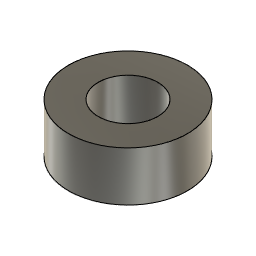
KOGUMA.MK3 (Autodesk Fusion 360 archive; units mm, degrees)
design "ベアリング（D６ｄ３）"
Autodesk Fusion 360 part; units mm, degrees
(part 1 of 8)
sketch "スケッチ1" plane through (0, 0, 0) normal (0, 0, 1) x (1, 0, 0)
  circle A0 centre (0, 0) radius 1.5
  circle A1 centre (0, 0) radius 3
  dimension "d1" = 3
  dimension "d2" = 6
  constraint coincident A0.centre A1.centre
  measures "d1" diameter of A0
  measures "d2" diameter of A1
extrude "押し出し1" add sketch "スケッチ1" along normal blind 2.5

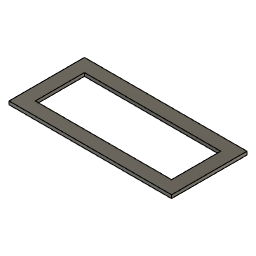
design "一次スカート"
Autodesk Fusion 360 part; units mm, degrees
sketch "スケッチ1" plane through (0, 0, 0) normal (0, 0, 1) x (1, 0, 0)
  line L0 (0, 0) -> (0, 15)
  line L1 (0, 15) -> (-41.568, 15)
  line L2 (-41.568, 15) -> (-41.568, 0)
  line L3 (-41.568, 0) -> (0, 0)
  line L4 (0, 0) -> (4, 0)
  line L5 (4, 0) -> (4, 1)
  line L6 (0, 15) -> (0, 19)
  line L7 (0, 19) -> (-64.5943, 19)
  line L8 (4, 0) -> (4, 52)
  line L9 (4, 19) -> (0, 19)
  line L10 (-41.568, 15) -> (-45.568, 15)
  line L11 (-45.568, 19) -> (-45.568, -8.7839)
  line L12 (-41.568, 0) -> (-41.568, -4)
  line L13 (-41.568, -4) -> (-45.568, -4)
  line L14 (-45.568, -4) -> (15, -4)
  line L15 (4, 0) -> (4, -9)
  dimension "d1" = 15
  dimension "d2" = 41.568
  dimension "d3" = 4
  dimension "d4" = 4
  dimension "d5" = 4
  dimension "d8" = 4
  dimension "d9" = 4
  constraint coincident L0.start L3.end
  constraint vertical L0
  constraint perpendicular L0 L1
  constraint perpendicular L1 L2
  constraint perpendicular L0 L3
  constraint perpendicular L0 L4
  constraint perpendicular L4 L5
  constraint perpendicular L1 L6
  constraint perpendicular L0 L7
  constraint perpendicular L4 L8
  constraint coincident L8 L9.start
  constraint perpendicular L6 L9
  constraint perpendicular L2 L10
  constraint coincident L7 L11.start
  constraint perpendicular L7 L11
  constraint perpendicular L3 L12
  constraint coincident L11 L13.end
  constraint perpendicular L11 L13
  constraint perpendicular L11 L14
  constraint perpendicular L14 L15
  measures "d1" distance of L0.start L0.end
  measures "d2" distance of L0.end L1.end
  measures "d3" distance of L0.start L4.end
  measures "d4" distance of L1.end L10.end
  measures "d5" distance of L2.end L12.end
  measures "d8" distance of L7 L10
  measures "d9" distance of L2 L11
extrude "押し出し1" add sketch "スケッチ1" along normal blind 1 contours L3 L4 L12 L14 L15 | L0 L4 L5 L6 L8 L9 | L1 L6 L7 L10 L11 | L2 L10 L11 L12 L13 L14
equation "d2 = ( 20.784 * 2 ) * 1 mm"

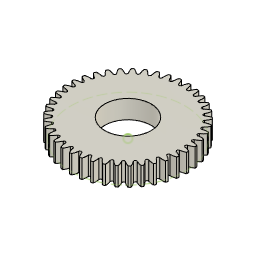
design "歯車M0.3T41"
description: Spur Gear; Module: 0.3; Num Teeth: 41; Pressure Angle: 20.0; Backlash: 0.00 mm
Autodesk Fusion 360 part; units mm, degrees
sketch "スケッチ1" plane through (0, 0, 0) normal (0, 0, 1) x (1, 0, 0) in component "Spur Gear (41 teeth)"
  circle A0 centre (0, 0) radius 5.7392
  circle A1 centre (0, 0) radius 0.5
extrude "押し出し1" add sketch "スケッチ1" along normal blind 2 contours A0 picked at (3.969571, -0.309968) in component "Spur Gear (41 teeth)"
sketch "スケッチ2" plane through (0, 0, 0) normal (0, 0, 1) x (1, 0, 0) in component "Spur Gear (41 teeth)"
  spline S0 degree 5 poles (5.770928, -0.307399) (5.77286, -0.307481) (5.776725, -0.30761) (5.782524, -0.307697) (5.79026, -0.307608) (5.799934, -0.307209) (5.809615, -0.30659) (5.819302, -0.30582) (5.828994, -0.304952) (5.838692, -0.304011) (5.848394, -0.303) (5.858099, -0.30191) (5.867807, -0.300726) (5.877517, -0.299436) (5.887228, -0.298039) (5.89694, -0.296542) (5.906654, -0.294955) (5.916369, -0.293289) (5.926086, -0.291553) (5.935804, -0.289752) (5.945522, -0.287885) (5.955241, -0.285952) (5.964961, -0.283951) (5.974681, -0.28188) (5.984401, -0.27974) (5.99412, -0.277533) (6.00384, -0.27526) (6.013559, -0.272926) (6.023279, -0.270532) (6.032997, -0.268079) (6.042715, -0.265569) (6.052432, -0.263001) (6.062149, -0.260375) (6.071864, -0.257693) (6.081578, -0.254954) (6.091292, -0.252159) (6.101003, -0.24931) (6.110714, -0.246406) (6.120423, -0.24345) (6.13013, -0.240441) (6.139836, -0.23738) (6.14954, -0.234268) (6.159242, -0.231105) (6.168942, -0.227891) (6.17864, -0.224627) (6.188336, -0.221314) (6.198029, -0.217951) (6.207721, -0.214539) (6.217409, -0.211079) (6.227096, -0.20757) (6.236779, -0.204015) (6.24646, -0.200412) (6.256138, -0.196762) (6.265814, -0.193065) (6.275486, -0.189323) (6.285155, -0.185534) (6.294822, -0.1817) (6.304485, -0.17782) (6.314144, -0.173896) (6.3238, -0.169926) (6.333453, -0.165912) (6.343102, -0.161854) (6.352748, -0.157752) (6.36239, -0.153607) (6.372028, -0.149418) (6.381663, -0.145185) (6.391293, -0.14091) (6.400919, -0.136592) (6.410541, -0.132232) (6.420159, -0.127829) (6.429773, -0.123385) (6.43746, -0.119795) (6.443224, -0.117084) (6.447066, -0.115268) (6.448986, -0.114359) knots 0 0 0 0 0 0 0.01428571 0.02857143 0.04285714 0.05714286 0.07142857 0.08571429 0.1 0.11428571 0.12857143 0.14285714 0.15714286 0.17142857 0.18571429 0.2 0.21428571 0.22857143 0.24285714 0.25714286 0.27142857 0.28571429 0.3 0.31428571 0.32857143 0.34285714 0.35714286 0.37142857 0.38571429 0.4 0.41428571 0.42857143 0.44285714 0.45714286 0.47142857 0.48571429 0.5 0.51428571 0.52857143 0.54285714 0.55714286 0.57142857 0.58571429 0.6 0.61428571 0.62857143 0.64285714 0.65714286 0.67142857 0.68571429 0.7 0.71428571 0.72857143 0.74285714 0.75714286 0.77142857 0.78571429 0.8 0.81428571 0.82857143 0.84285714 0.85714286 0.87142857 0.88571429 0.9 0.91428571 0.92857143 0.94285714 0.95714286 0.97142857 0.98571429 1 1 1 1 1 1
  spline S1 degree 5 poles (5.770928, 0.307399) (5.77286, 0.307481) (5.776725, 0.30761) (5.782524, 0.307697) (5.79026, 0.307608) (5.799934, 0.307209) (5.809615, 0.30659) (5.819302, 0.30582) (5.828994, 0.304952) (5.838692, 0.304011) (5.848394, 0.303) (5.858099, 0.30191) (5.867807, 0.300726) (5.877517, 0.299436) (5.887228, 0.298039) (5.89694, 0.296542) (5.906654, 0.294955) (5.916369, 0.293289) (5.926086, 0.291553) (5.935804, 0.289752) (5.945522, 0.287885) (5.955241, 0.285952) (5.964961, 0.283951) (5.974681, 0.28188) (5.984401, 0.27974) (5.99412, 0.277533) (6.00384, 0.27526) (6.013559, 0.272926) (6.023279, 0.270532) (6.032997, 0.268079) (6.042715, 0.265569) (6.052432, 0.263001) (6.062149, 0.260375) (6.071864, 0.257693) (6.081578, 0.254954) (6.091292, 0.252159) (6.101003, 0.24931) (6.110714, 0.246406) (6.120423, 0.24345) (6.13013, 0.240441) (6.139836, 0.23738) (6.14954, 0.234268) (6.159242, 0.231105) (6.168942, 0.227891) (6.17864, 0.224627) (6.188336, 0.221314) (6.198029, 0.217951) (6.207721, 0.214539) (6.217409, 0.211079) (6.227096, 0.20757) (6.236779, 0.204015) (6.24646, 0.200412) (6.256138, 0.196762) (6.265814, 0.193065) (6.275486, 0.189323) (6.285155, 0.185534) (6.294822, 0.1817) (6.304485, 0.17782) (6.314144, 0.173896) (6.3238, 0.169926) (6.333453, 0.165912) (6.343102, 0.161854) (6.352748, 0.157752) (6.36239, 0.153607) (6.372028, 0.149418) (6.381663, 0.145185) (6.391293, 0.14091) (6.400919, 0.136592) (6.410541, 0.132232) (6.420159, 0.127829) (6.429773, 0.123385) (6.43746, 0.119795) (6.443224, 0.117084) (6.447066, 0.115268) (6.448986, 0.114359) knots 0 0 0 0 0 0 0.01428571 0.02857143 0.04285714 0.05714286 0.07142857 0.08571429 0.1 0.11428571 0.12857143 0.14285714 0.15714286 0.17142857 0.18571429 0.2 0.21428571 0.22857143 0.24285714 0.25714286 0.27142857 0.28571429 0.3 0.31428571 0.32857143 0.34285714 0.35714286 0.37142857 0.38571429 0.4 0.41428571 0.42857143 0.44285714 0.45714286 0.47142857 0.48571429 0.5 0.51428571 0.52857143 0.54285714 0.55714286 0.57142857 0.58571429 0.6 0.61428571 0.62857143 0.64285714 0.65714286 0.67142857 0.68571429 0.7 0.71428571 0.72857143 0.74285714 0.75714286 0.77142857 0.78571429 0.8 0.81428571 0.82857143 0.84285714 0.85714286 0.87142857 0.88571429 0.9 0.91428571 0.92857143 0.94285714 0.95714286 0.97142857 0.98571429 1 1 1 1 1 1
  arc A0 (6.448986, -0.114359) -> (6.448986, 0.114359) centre (0, 0) ccw
  line L0 (5.721089, -0.305276) -> (5.770928, -0.307399)
  line L1 (5.721089, 0.305276) -> (5.770928, 0.307399)
  line L2 (5.721089, -0.305276) -> (5.721089, 0.305276)
  point P0 (5.819, -0.305821)
  point P1 (5.867247, -0.300771)
  point P2 (5.9156, -0.293406)
  point P3 (5.964028, -0.284129)
  point P4 (6.012511, -0.273166)
  point P5 (6.061031, -0.260666)
  point P6 (6.109575, -0.246736)
  point P7 (6.158127, -0.231458)
  point P8 (6.206677, -0.214896)
  point P9 (6.255212, -0.197101)
  point P10 (6.303722, -0.178116)
  point P11 (6.352194, -0.157978)
  point P12 (6.400619, -0.136716)
  point P13 (5.819, 0.305821)
  point P14 (5.867247, 0.300771)
  point P15 (5.9156, 0.293406)
  point P16 (5.964028, 0.284129)
  point P17 (6.012511, 0.273166)
  point P18 (6.061031, 0.260666)
  point P19 (6.109575, 0.246736)
  point P20 (6.158127, 0.231458)
  point P21 (6.206677, 0.214896)
  point P22 (6.255212, 0.197101)
  point P23 (6.303722, 0.178116)
  point P24 (6.352194, 0.157978)
  point P25 (6.400619, 0.136716)
extrude "押し出し2" add sketch "スケッチ2" along normal blind 2 contours S0 S1 A0 L0 L1 L2 picked at (6.064498, 0.076046) in component "Spur Gear (41 teeth)"
fillet "フィレット1" radius 0.15 2 edges at (5.731053, -0.3057, 1) (5.731053, 0.3057, 1) in component "Spur Gear (41 teeth)"
pattern_circular "C パターン1" count 41 over 360 about axis through (0, 0, 0) along (0, 0, 1) of "押し出し2", "フィレット1" in component "Spur Gear (41 teeth)"
sketch "スケッチ3" plane through (0, 0, 0) normal (0, 0, 1) x (1, 0, 0) in component "Spur Gear (41 teeth)"
  circle A0 centre (0, 0) radius 6.15 construction
sketch "スケッチ1 (2)" plane through (0, 0, 2) normal (0, 0, 1) x (-1, 0, 0)
  spline S0 degree 5 poles (-5.857066, 0.302007) (-5.857273, 0.301983) (-5.859421, 0.301733) (-5.86351, 0.301246) (-5.869542, 0.300495) (-5.877517, 0.299436) (-5.887228, 0.298039) (-5.89694, 0.296542) (-5.906654, 0.294955) (-5.916369, 0.293289) (-5.926086, 0.291553) (-5.935804, 0.289752) (-5.945522, 0.287885) (-5.955241, 0.285952) (-5.964961, 0.283951) (-5.974681, 0.28188) (-5.984401, 0.27974) (-5.99412, 0.277533) (-6.00384, 0.27526) (-6.013559, 0.272926) (-6.023279, 0.270532) (-6.032997, 0.268079) (-6.042715, 0.265569) (-6.052432, 0.263001) (-6.062149, 0.260375) (-6.071864, 0.257693) (-6.081578, 0.254954) (-6.091292, 0.252159) (-6.101003, 0.24931) (-6.110714, 0.246406) (-6.120423, 0.24345) (-6.13013, 0.240441) (-6.139836, 0.23738) (-6.14954, 0.234268) (-6.159242, 0.231105) (-6.168942, 0.227891) (-6.17864, 0.224627) (-6.188336, 0.221314) (-6.198029, 0.217951) (-6.207721, 0.214539) (-6.217409, 0.211079) (-6.227096, 0.20757) (-6.236779, 0.204015) (-6.24646, 0.200412) (-6.256138, 0.196762) (-6.265814, 0.193065) (-6.275486, 0.189323) (-6.285155, 0.185534) (-6.294822, 0.1817) (-6.304485, 0.17782) (-6.314144, 0.173896) (-6.3238, 0.169926) (-6.333453, 0.165912) (-6.343102, 0.161854) (-6.352748, 0.157752) (-6.36239, 0.153607) (-6.372028, 0.149418) (-6.381663, 0.145185) (-6.391293, 0.14091) (-6.400919, 0.136592) (-6.410541, 0.132232) (-6.420159, 0.127829) (-6.429773, 0.123385) (-6.43746, 0.119795) (-6.443224, 0.117084) (-6.447066, 0.115268) (-6.448986, 0.114359) knots 0.1270499 0.1270499 0.1270499 0.1270499 0.1270499 0.1270499 0.12857143 0.14285714 0.15714286 0.17142857 0.18571429 0.2 0.21428571 0.22857143 0.24285714 0.25714286 0.27142857 0.28571429 0.3 0.31428571 0.32857143 0.34285714 0.35714286 0.37142857 0.38571429 0.4 0.41428571 0.42857143 0.44285714 0.45714286 0.47142857 0.48571429 0.5 0.51428571 0.52857143 0.54285714 0.55714286 0.57142857 0.58571429 0.6 0.61428571 0.62857143 0.64285714 0.65714286 0.67142857 0.68571429 0.7 0.71428571 0.72857143 0.74285714 0.75714286 0.77142857 0.78571429 0.8 0.81428571 0.82857143 0.84285714 0.85714286 0.87142857 0.88571429 0.9 0.91428571 0.92857143 0.94285714 0.95714286 0.97142857 0.98571429 1 1 1 1 1 1
  arc A0 (-6.448986, 0.114359) -> (-6.448986, -0.114359) centre (0, 0) ccw
  spline S1 degree 5 poles (-6.448986, -0.114359) (-6.447066, -0.115268) (-6.443224, -0.117084) (-6.43746, -0.119795) (-6.429773, -0.123385) (-6.420159, -0.127829) (-6.410541, -0.132232) (-6.400919, -0.136592) (-6.391293, -0.14091) (-6.381663, -0.145185) (-6.372028, -0.149418) (-6.36239, -0.153607) (-6.352748, -0.157752) (-6.343102, -0.161854) (-6.333453, -0.165912) (-6.3238, -0.169926) (-6.314144, -0.173896) (-6.304485, -0.17782) (-6.294822, -0.1817) (-6.285155, -0.185534) (-6.275486, -0.189323) (-6.265814, -0.193065) (-6.256138, -0.196762) (-6.24646, -0.200412) (-6.236779, -0.204015) (-6.227096, -0.20757) (-6.217409, -0.211079) (-6.207721, -0.214539) (-6.198029, -0.217951) (-6.188336, -0.221314) (-6.17864, -0.224627) (-6.168942, -0.227891) (-6.159242, -0.231105) (-6.14954, -0.234268) (-6.139836, -0.23738) (-6.13013, -0.240441) (-6.120423, -0.24345) (-6.110714, -0.246406) (-6.101003, -0.24931) (-6.091292, -0.252159) (-6.081578, -0.254954) (-6.071864, -0.257693) (-6.062149, -0.260375) (-6.052432, -0.263001) (-6.042715, -0.265569) (-6.032997, -0.268079) (-6.023279, -0.270532) (-6.013559, -0.272926) (-6.00384, -0.27526) (-5.99412, -0.277533) (-5.984401, -0.27974) (-5.974681, -0.28188) (-5.964961, -0.283951) (-5.955241, -0.285952) (-5.945522, -0.287885) (-5.935804, -0.289752) (-5.926086, -0.291553) (-5.916369, -0.293289) (-5.906654, -0.294955) (-5.89694, -0.296542) (-5.887228, -0.298039) (-5.877517, -0.299436) (-5.869542, -0.300495) (-5.86351, -0.301246) (-5.859421, -0.301733) (-5.857273, -0.301983) (-5.857066, -0.302007) knots -1 -1 -1 -1 -1 -1 -0.98571429 -0.97142857 -0.95714286 -0.94285714 -0.92857143 -0.91428571 -0.9 -0.88571429 -0.87142857 -0.85714286 -0.84285714 -0.82857143 -0.81428571 -0.8 -0.78571429 -0.77142857 -0.75714286 -0.74285714 -0.72857143 -0.71428571 -0.7 -0.68571429 -0.67142857 -0.65714286 -0.64285714 -0.62857143 -0.61428571 -0.6 -0.58571429 -0.57142857 -0.55714286 -0.54285714 -0.52857143 -0.51428571 -0.5 -0.48571429 -0.47142857 -0.45714286 -0.44285714 -0.42857143 -0.41428571 -0.4 -0.38571429 -0.37142857 -0.35714286 -0.34285714 -0.32857143 -0.31428571 -0.3 -0.28571429 -0.27142857 -0.25714286 -0.24285714 -0.22857143 -0.21428571 -0.2 -0.18571429 -0.17142857 -0.15714286 -0.14285714 -0.12857143 -0.1270499 -0.1270499 -0.1270499 -0.1270499 -0.1270499 -0.1270499
  spline S2 degree 3 poles (-5.834525, -0.595609) (-5.815695, -0.590418) (-5.798059, -0.581599) (-5.76716, -0.557697) (-5.754193, -0.542842) (-5.734682, -0.508999) (-5.728326, -0.490334) (-5.723124, -0.451617) (-5.724329, -0.431936) (-5.734216, -0.394144) (-5.742803, -0.376393) (-5.766298, -0.345184) (-5.780981, -0.332023) (-5.806816, -0.316674) (-5.816398, -0.312267) (-5.836327, -0.305532) (-5.846618, -0.303222) (-5.857066, -0.302007) knots 0 0 0 0 0.00585967 0.00585967 0.01171933 0.01171933 0.017579 0.017579 0.02343867 0.02343867 0.02929834 0.02929834 0.035158 0.035158 0.03831344 0.03831344 0.04146887 0.04146887 0.04146887 0.04146887
  spline S3 degree 5 poles (-5.834525, -0.595609) (-5.834725, -0.595664) (-5.83681, -0.59624) (-5.840777, -0.597346) (-5.846624, -0.599008) (-5.854343, -0.601272) (-5.863727, -0.604135) (-5.873098, -0.607097) (-5.882455, -0.610148) (-5.891802, -0.613278) (-5.90114, -0.616476) (-5.910469, -0.61974) (-5.919789, -0.623068) (-5.929099, -0.626462) (-5.938399, -0.629924) (-5.947689, -0.633454) (-5.956968, -0.637053) (-5.966237, -0.640718) (-5.975496, -0.644447) (-5.984745, -0.648238) (-5.993985, -0.652088) (-6.003215, -0.655995) (-6.012436, -0.65996) (-6.021647, -0.663981) (-6.030849, -0.668059) (-6.040041, -0.672193) (-6.049223, -0.676383) (-6.058396, -0.680627) (-6.067559, -0.684926) (-6.076713, -0.689278) (-6.085857, -0.693681) (-6.094991, -0.698137) (-6.104116, -0.702643) (-6.113231, -0.7072) (-6.122336, -0.711807) (-6.131432, -0.716464) (-6.140518, -0.72117) (-6.149595, -0.725925) (-6.158661, -0.730728) (-6.167718, -0.73558) (-6.176765, -0.740478) (-6.185802, -0.745424) (-6.19483, -0.750416) (-6.203847, -0.755455) (-6.212855, -0.760539) (-6.221852, -0.765669) (-6.23084, -0.770845) (-6.239818, -0.776065) (-6.248785, -0.78133) (-6.257743, -0.786639) (-6.26669, -0.791992) (-6.275627, -0.797389) (-6.284554, -0.802829) (-6.293471, -0.808312) (-6.302377, -0.813839) (-6.311274, -0.819408) (-6.320159, -0.825019) (-6.329035, -0.830672) (-6.337899, -0.836368) (-6.346754, -0.842104) (-6.355597, -0.847882) (-6.36443, -0.853701) (-6.373253, -0.859562) (-6.380302, -0.864282) (-6.385585, -0.867841) (-6.389104, -0.870222) (-6.390863, -0.871415) knots 0.1270499 0.1270499 0.1270499 0.1270499 0.1270499 0.1270499 0.12857143 0.14285714 0.15714286 0.17142857 0.18571429 0.2 0.21428571 0.22857143 0.24285714 0.25714286 0.27142857 0.28571429 0.3 0.31428571 0.32857143 0.34285714 0.35714286 0.37142857 0.38571429 0.4 0.41428571 0.42857143 0.44285714 0.45714286 0.47142857 0.48571429 0.5 0.51428571 0.52857143 0.54285714 0.55714286 0.57142857 0.58571429 0.6 0.61428571 0.62857143 0.64285714 0.65714286 0.67142857 0.68571429 0.7 0.71428571 0.72857143 0.74285714 0.75714286 0.77142857 0.78571429 0.8 0.81428571 0.82857143 0.84285714 0.85714286 0.87142857 0.88571429 0.9 0.91428571 0.92857143 0.94285714 0.95714286 0.97142857 0.98571429 1 1 1 1 1 1
  arc A1 (-6.390863, -0.871415) -> (-6.35595, -1.097451) centre (0, 0) ccw
  spline S4 degree 5 poles (-6.35595, -1.097451) (-6.353913, -1.098058) (-6.349839, -1.099266) (-6.343729, -1.101065) (-6.335584, -1.103439) (-6.325404, -1.106364) (-6.315227, -1.109247) (-6.305052, -1.112087) (-6.29488, -1.114885) (-6.28471, -1.11764) (-6.274542, -1.120352) (-6.264378, -1.123021) (-6.254216, -1.125646) (-6.244057, -1.128228) (-6.233901, -1.130765) (-6.223749, -1.133258) (-6.2136, -1.135707) (-6.203455, -1.138111) (-6.193313, -1.14047) (-6.183174, -1.142784) (-6.17304, -1.145052) (-6.16291, -1.147275) (-6.152784, -1.149451) (-6.142662, -1.151581) (-6.132544, -1.153664) (-6.122431, -1.1557) (-6.112323, -1.157688) (-6.10222, -1.159629) (-6.092121, -1.161521) (-6.082028, -1.163365) (-6.07194, -1.16516) (-6.061857, -1.166905) (-6.05178, -1.168601) (-6.041709, -1.170246) (-6.031644, -1.17184) (-6.021585, -1.173383) (-6.011532, -1.174875) (-6.001485, -1.176315) (-5.991445, -1.177702) (-5.981412, -1.179035) (-5.971386, -1.180314) (-5.961368, -1.181538) (-5.951357, -1.182706) (-5.941354, -1.183818) (-5.931358, -1.184872) (-5.921371, -1.18587) (-5.911392, -1.18681) (-5.901421, -1.187693) (-5.891459, -1.188516) (-5.881507, -1.189278) (-5.871564, -1.189976) (-5.861631, -1.190608) (-5.851709, -1.19117) (-5.841798, -1.191664) (-5.831898, -1.192091) (-5.822008, -1.192452) (-5.812129, -1.192749) (-5.802262, -1.192981) (-5.792406, -1.193145) (-5.782564, -1.193231) (-5.772736, -1.193227) (-5.762926, -1.193125) (-5.754883, -1.192955) (-5.748807, -1.192776) (-5.744691, -1.192633) (-5.74253, -1.192552) (-5.742322, -1.192545) knots -1 -1 -1 -1 -1 -1 -0.98571429 -0.97142857 -0.95714286 -0.94285714 -0.92857143 -0.91428571 -0.9 -0.88571429 -0.87142857 -0.85714286 -0.84285714 -0.82857143 -0.81428571 -0.8 -0.78571429 -0.77142857 -0.75714286 -0.74285714 -0.72857143 -0.71428571 -0.7 -0.68571429 -0.67142857 -0.65714286 -0.64285714 -0.62857143 -0.61428571 -0.6 -0.58571429 -0.57142857 -0.55714286 -0.54285714 -0.52857143 -0.51428571 -0.5 -0.48571429 -0.47142857 -0.45714286 -0.44285714 -0.42857143 -0.41428571 -0.4 -0.38571429 -0.37142857 -0.35714286 -0.34285714 -0.32857143 -0.31428571 -0.3 -0.28571429 -0.27142857 -0.25714286 -0.24285714 -0.22857143 -0.21428571 -0.2 -0.18571429 -0.17142857 -0.15714286 -0.14285714 -0.12857143 -0.1270499 -0.1270499 -0.1270499 -0.1270499 -0.1270499 -0.1270499
  spline S5 degree 3 poles (-5.675227, -1.479265) (-5.65741, -1.47126) (-5.641328, -1.459852) (-5.61444, -1.431514) (-5.603892, -1.414854) (-5.589776, -1.378429) (-5.586343, -1.359012) (-5.587113, -1.319955) (-5.591308, -1.300689) (-5.606848, -1.264848) (-5.618044, -1.248617) (-5.646027, -1.22136) (-5.662547, -1.210594) (-5.690422, -1.199369) (-5.700565, -1.196477) (-5.721289, -1.192863) (-5.731812, -1.19215) (-5.742322, -1.192545) knots 0 0 0 0 0.00585967 0.00585967 0.01171933 0.01171933 0.017579 0.017579 0.02343867 0.02343867 0.02929834 0.02929834 0.035158 0.035158 0.03831344 0.03831344 0.04146887 0.04146887 0.04146887 0.04146887
  spline S6 degree 5 poles (-5.675227, -1.479265) (-5.675417, -1.47935) (-5.677389, -1.480237) (-5.681141, -1.481935) (-5.686666, -1.484471) (-5.693949, -1.487887) (-5.702786, -1.492148) (-5.711595, -1.496506) (-5.720377, -1.50095) (-5.729137, -1.50547) (-5.737877, -1.510056) (-5.746598, -1.514706) (-5.7553, -1.519418) (-5.763983, -1.524193) (-5.772646, -1.529033) (-5.781288, -1.533941) (-5.789909, -1.538914) (-5.79851, -1.543951) (-5.807091, -1.54905) (-5.815653, -1.554208) (-5.824197, -1.559423) (-5.832723, -1.564694) (-5.84123, -1.570019) (-5.84972, -1.5754) (-5.858191, -1.580834) (-5.866645, -1.586323) (-5.87508, -1.591866) (-5.883497, -1.597461) (-5.891896, -1.603108) (-5.900278, -1.608805) (-5.908643, -1.614553) (-5.91699, -1.620351) (-5.92532, -1.626197) (-5.933633, -1.632092) (-5.941928, -1.638035) (-5.950207, -1.644026) (-5.958468, -1.650064) (-5.966712, -1.656149) (-5.974939, -1.66228) (-5.983149, -1.668457) (-5.991342, -1.674679) (-5.999519, -1.680946) (-6.007678, -1.687258) (-6.015821, -1.693614) (-6.023947, -1.700014) (-6.032056, -1.706457) (-6.040148, -1.712944) (-6.048224, -1.719473) (-6.056283, -1.726045) (-6.064325, -1.73266) (-6.07235, -1.739316) (-6.080359, -1.746014) (-6.088351, -1.752753) (-6.096326, -1.759533) (-6.104284, -1.766354) (-6.112226, -1.773216) (-6.120151, -1.780118) (-6.128059, -1.78706) (-6.135951, -1.794041) (-6.143826, -1.801063) (-6.151684, -1.808123) (-6.159525, -1.815222) (-6.16735, -1.82236) (-6.173596, -1.828102) (-6.178273, -1.832426) (-6.181388, -1.835316) (-6.182944, -1.836763) knots 0.1270499 0.1270499 0.1270499 0.1270499 0.1270499 0.1270499 0.12857143 0.14285714 0.15714286 0.17142857 0.18571429 0.2 0.21428571 0.22857143 0.24285714 0.25714286 0.27142857 0.28571429 0.3 0.31428571 0.32857143 0.34285714 0.35714286 0.37142857 0.38571429 0.4 0.41428571 0.42857143 0.44285714 0.45714286 0.47142857 0.48571429 0.5 0.51428571 0.52857143 0.54285714 0.55714286 0.57142857 0.58571429 0.6 0.61428571 0.62857143 0.64285714 0.65714286 0.67142857 0.68571429 0.7 0.71428571 0.72857143 0.74285714 0.75714286 0.77142857 0.78571429 0.8 0.81428571 0.82857143 0.84285714 0.85714286 0.87142857 0.88571429 0.9 0.91428571 0.92857143 0.94285714 0.95714286 0.97142857 0.98571429 1 1 1 1 1 1
  arc A2 (-6.182944, -1.836763) -> (-6.113936, -2.054821) centre (0, 0) ccw
  spline S7 degree 5 poles (-6.113936, -2.054821) (-6.11183, -2.055109) (-6.10762, -2.055681) (-6.101307, -2.056527) (-6.092894, -2.057629) (-6.082388, -2.058966) (-6.07189, -2.060262) (-6.0614, -2.061516) (-6.05092, -2.062728) (-6.040449, -2.063898) (-6.029986, -2.065026) (-6.019533, -2.066112) (-6.00909, -2.067156) (-5.998656, -2.068156) (-5.988232, -2.069114) (-5.977818, -2.070028) (-5.967414, -2.070899) (-5.957021, -2.071726) (-5.946638, -2.072509) (-5.936265, -2.073248) (-5.925903, -2.073943) (-5.915552, -2.074593) (-5.905213, -2.075198) (-5.894884, -2.075758) (-5.884567, -2.076272) (-5.874262, -2.07674) (-5.863969, -2.077162) (-5.853688, -2.077538) (-5.843419, -2.077866) (-5.833162, -2.078148) (-5.822918, -2.078382) (-5.812688, -2.078568) (-5.80247, -2.078705) (-5.792266, -2.078793) (-5.782075, -2.078833) (-5.771898, -2.078822) (-5.761735, -2.078762) (-5.751587, -2.078651) (-5.741453, -2.078489) (-5.731334, -2.078276) (-5.72123, -2.078009) (-5.711142, -2.07769) (-5.70107, -2.077316) (-5.691014, -2.076887) (-5.680975, -2.076404) (-5.670953, -2.075865) (-5.660947, -2.075271) (-5.650959, -2.074621) (-5.640988, -2.073914) (-5.631035, -2.073148) (-5.621103, -2.07232) (-5.61119, -2.071428) (-5.601298, -2.07047) (-5.591428, -2.069445) (-5.581578, -2.068355) (-5.57175, -2.067202) (-5.561941, -2.065988) (-5.552154, -2.064711) (-5.542389, -2.063368) (-5.532649, -2.061951) (-5.522937, -2.060447) (-5.513257, -2.058849) (-5.505335, -2.057453) (-5.499357, -2.056348) (-5.495311, -2.055579) (-5.493188, -2.055169) (-5.492984, -2.05513) knots -1 -1 -1 -1 -1 -1 -0.98571429 -0.97142857 -0.95714286 -0.94285714 -0.92857143 -0.91428571 -0.9 -0.88571429 -0.87142857 -0.85714286 -0.84285714 -0.82857143 -0.81428571 -0.8 -0.78571429 -0.77142857 -0.75714286 -0.74285714 -0.72857143 -0.71428571 -0.7 -0.68571429 -0.67142857 -0.65714286 -0.64285714 -0.62857143 -0.61428571 -0.6 -0.58571429 -0.57142857 -0.55714286 -0.54285714 -0.52857143 -0.51428571 -0.5 -0.48571429 -0.47142857 -0.45714286 -0.44285714 -0.42857143 -0.41428571 -0.4 -0.38571429 -0.37142857 -0.35714286 -0.34285714 -0.32857143 -0.31428571 -0.3 -0.28571429 -0.27142857 -0.25714286 -0.24285714 -0.22857143 -0.21428571 -0.2 -0.18571429 -0.17142857 -0.15714286 -0.14285714 -0.12857143 -0.1270499 -0.1270499 -0.1270499 -0.1270499 -0.1270499 -0.1270499
  spline S8 degree 3 poles (-5.382907, -2.328248) (-5.366521, -2.317618) (-5.352368, -2.303888) (-5.330121, -2.271777) (-5.32224, -2.253703) (-5.31385, -2.21555) (-5.313421, -2.195836) (-5.320144, -2.157355) (-5.327231, -2.138955) (-5.34806, -2.105906) (-5.361602, -2.091574) (-5.393419, -2.068908) (-5.411388, -2.06079) (-5.44065, -2.053952) (-5.451116, -2.052642) (-5.472148, -2.052233) (-5.482656, -2.053136) (-5.492984, -2.05513) knots 0 0 0 0 0.00585967 0.00585967 0.01171933 0.01171933 0.017579 0.017579 0.02343867 0.02343867 0.02929834 0.02929834 0.035158 0.035158 0.03831344 0.03831344 0.04146887 0.04146887 0.04146887 0.04146887
  spline S9 degree 5 poles (-5.382907, -2.328248) (-5.383082, -2.328361) (-5.384896, -2.329539) (-5.388344, -2.33179) (-5.393417, -2.335139) (-5.400093, -2.339627) (-5.408177, -2.345187) (-5.416216, -2.350839) (-5.424218, -2.356571) (-5.432185, -2.362375) (-5.440122, -2.368242) (-5.448031, -2.374168) (-5.455912, -2.380153) (-5.463765, -2.386198) (-5.471587, -2.392304) (-5.479379, -2.398473) (-5.48714, -2.404704) (-5.494871, -2.410995) (-5.502573, -2.417344) (-5.510248, -2.423749) (-5.517895, -2.430207) (-5.525516, -2.436717) (-5.533111, -2.443279) (-5.54068, -2.449892) (-5.548223, -2.456556) (-5.555739, -2.463271) (-5.563229, -2.470036) (-5.570694, -2.476851) (-5.578133, -2.483714) (-5.585547, -2.490624) (-5.592936, -2.497582) (-5.6003, -2.504585) (-5.60764, -2.511635) (-5.614955, -2.51873) (-5.622246, -2.525869) (-5.629513, -2.533053) (-5.636756, -2.540282) (-5.643975, -2.547554) (-5.651169, -2.554869) (-5.658341, -2.562227) (-5.665488, -2.569627) (-5.672612, -2.577068) (-5.679712, -2.584552) (-5.686789, -2.592076) (-5.693843, -2.599642) (-5.700873, -2.607247) (-5.707881, -2.614893) (-5.714865, -2.622579) (-5.721826, -2.630304) (-5.728764, -2.638069) (-5.735679, -2.645872) (-5.742572, -2.653714) (-5.749441, -2.661594) (-5.756288, -2.669512) (-5.763112, -2.677468) (-5.769913, -2.685462) (-5.776692, -2.693492) (-5.783448, -2.70156) (-5.790181, -2.709665) (-5.796892, -2.717805) (-5.80358, -2.725983) (-5.810246, -2.734196) (-5.816889, -2.742445) (-5.822186, -2.749072) (-5.826148, -2.754059) (-5.828785, -2.757391) (-5.830102, -2.759059) knots 0.1270499 0.1270499 0.1270499 0.1270499 0.1270499 0.1270499 0.12857143 0.14285714 0.15714286 0.17142857 0.18571429 0.2 0.21428571 0.22857143 0.24285714 0.25714286 0.27142857 0.28571429 0.3 0.31428571 0.32857143 0.34285714 0.35714286 0.37142857 0.38571429 0.4 0.41428571 0.42857143 0.44285714 0.45714286 0.47142857 0.48571429 0.5 0.51428571 0.52857143 0.54285714 0.55714286 0.57142857 0.58571429 0.6 0.61428571 0.62857143 0.64285714 0.65714286 0.67142857 0.68571429 0.7 0.71428571 0.72857143 0.74285714 0.75714286 0.77142857 0.78571429 0.8 0.81428571 0.82857143 0.84285714 0.85714286 0.87142857 0.88571429 0.9 0.91428571 0.92857143 0.94285714 0.95714286 0.97142857 0.98571429 1 1 1 1 1 1
  arc A3 (-5.830102, -2.759059) -> (-5.728616, -2.964027) centre (0, 0) ccw
  spline S10 degree 5 poles (-5.728616, -2.964027) (-5.726491, -2.963991) (-5.722243, -2.963913) (-5.715875, -2.963785) (-5.707393, -2.963591) (-5.696805, -2.963308) (-5.686232, -2.962986) (-5.675675, -2.962624) (-5.665132, -2.962222) (-5.654605, -2.96178) (-5.644093, -2.961298) (-5.633597, -2.960776) (-5.623116, -2.960213) (-5.612652, -2.959609) (-5.602204, -2.958964) (-5.591772, -2.958278) (-5.581358, -2.95755) (-5.57096, -2.956781) (-5.560579, -2.95597) (-5.550215, -2.955117) (-5.539868, -2.954222) (-5.52954, -2.953284) (-5.519229, -2.952304) (-5.508936, -2.95128) (-5.498661, -2.950214) (-5.488406, -2.949103) (-5.478168, -2.947949) (-5.46795, -2.946751) (-5.457751, -2.945508) (-5.447572, -2.944221) (-5.437413, -2.942889) (-5.427273, -2.94151) (-5.417155, -2.940086) (-5.407056, -2.938616) (-5.396979, -2.937099) (-5.386923, -2.935535) (-5.376889, -2.933924) (-5.366876, -2.932266) (-5.356886, -2.930559) (-5.346918, -2.928803) (-5.336973, -2.926998) (-5.327052, -2.925142) (-5.317155, -2.923235) (-5.307283, -2.921276) (-5.297435, -2.919266) (-5.287612, -2.917204) (-5.277814, -2.915089) (-5.268042, -2.912922) (-5.258296, -2.910702) (-5.248578, -2.908425) (-5.238887, -2.906091) (-5.229227, -2.903696) (-5.219598, -2.901239) (-5.209999, -2.898719) (-5.200432, -2.896139) (-5.190894, -2.893499) (-5.181386, -2.890802) (-5.171908, -2.888046) (-5.162463, -2.885228) (-5.153053, -2.88234) (-5.143685, -2.879372) (-5.134362, -2.876315) (-5.126746, -2.873726) (-5.121007, -2.871722) (-5.117126, -2.870344) (-5.11509, -2.869615) (-5.114894, -2.869545) knots -1 -1 -1 -1 -1 -1 -0.98571429 -0.97142857 -0.95714286 -0.94285714 -0.92857143 -0.91428571 -0.9 -0.88571429 -0.87142857 -0.85714286 -0.84285714 -0.82857143 -0.81428571 -0.8 -0.78571429 -0.77142857 -0.75714286 -0.74285714 -0.72857143 -0.71428571 -0.7 -0.68571429 -0.67142857 -0.65714286 -0.64285714 -0.62857143 -0.61428571 -0.6 -0.58571429 -0.57142857 -0.55714286 -0.54285714 -0.52857143 -0.51428571 -0.5 -0.48571429 -0.47142857 -0.45714286 -0.44285714 -0.42857143 -0.41428571 -0.4 -0.38571429 -0.37142857 -0.35714286 -0.34285714 -0.32857143 -0.31428571 -0.3 -0.28571429 -0.27142857 -0.25714286 -0.24285714 -0.22857143 -0.21428571 -0.2 -0.18571429 -0.17142857 -0.15714286 -0.14285714 -0.12857143 -0.1270499 -0.1270499 -0.1270499 -0.1270499 -0.1270499 -0.1270499
  spline S11 degree 3 poles (-4.964416, -3.122659) (-4.949845, -3.109652) (-4.937954, -3.093923) (-4.920869, -3.058792) (-4.91584, -3.039726) (-4.913372, -3.00074) (-4.915957, -2.981192) (-4.928475, -2.944188) (-4.938288, -2.927085) (-4.963918, -2.897603) (-4.979489, -2.885507) (-5.014393, -2.867963) (-5.033391, -2.862683) (-5.063354, -2.860392) (-5.073896, -2.860695) (-5.094745, -2.863501) (-5.104992, -2.865997) (-5.114894, -2.869545) knots 0 0 0 0 0.00585967 0.00585967 0.01171933 0.01171933 0.017579 0.017579 0.02343867 0.02343867 0.02929834 0.02929834 0.035158 0.035158 0.03831344 0.03831344 0.04146887 0.04146887 0.04146887 0.04146887
  spline S12 degree 5 poles (-4.964416, -3.122659) (-4.964572, -3.122797) (-4.966185, -3.124238) (-4.969249, -3.126989) (-4.973751, -3.131073) (-4.979664, -3.136528) (-4.986804, -3.143257) (-4.993887, -3.150069) (-5.000919, -3.156956) (-5.007907, -3.163908) (-5.014856, -3.170918) (-5.021768, -3.177982) (-5.028643, -3.1851) (-5.03548, -3.192273) (-5.042279, -3.199501) (-5.049038, -3.206787) (-5.055757, -3.21413) (-5.062437, -3.221527) (-5.069079, -3.228978) (-5.075686, -3.236479) (-5.082258, -3.244029) (-5.088796, -3.251626) (-5.095301, -3.25927) (-5.101771, -3.266961) (-5.108208, -3.274699) (-5.114611, -3.282482) (-5.120981, -3.290311) (-5.127318, -3.298185) (-5.133622, -3.306104) (-5.139894, -3.314065) (-5.146135, -3.322069) (-5.152344, -3.330115) (-5.158522, -3.338202) (-5.164668, -3.34633) (-5.170784, -3.354499) (-5.176869, -3.362708) (-5.182923, -3.370958) (-5.188947, -3.379246) (-5.194941, -3.387574) (-5.200905, -3.39594) (-5.206839, -3.404344) (-5.212744, -3.412786) (-5.218618, -3.421266) (-5.224464, -3.429783) (-5.23028, -3.438336) (-5.236067, -3.446926) (-5.241825, -3.455552) (-5.247554, -3.464213) (-5.253255, -3.472911) (-5.258926, -3.481643) (-5.264569, -3.490411) (-5.270184, -3.499213) (-5.27577, -3.508049) (-5.281328, -3.51692) (-5.286857, -3.525824) (-5.292359, -3.534762) (-5.297832, -3.543734) (-5.303277, -3.552738) (-5.308694, -3.561776) (-5.314084, -3.570845) (-5.319445, -3.579948) (-5.324779, -3.589082) (-5.330085, -3.598248) (-5.334308, -3.605607) (-5.337463, -3.61114) (-5.33956, -3.614836) (-5.340608, -3.616685) knots 0.1270499 0.1270499 0.1270499 0.1270499 0.1270499 0.1270499 0.12857143 0.14285714 0.15714286 0.17142857 0.18571429 0.2 0.21428571 0.22857143 0.24285714 0.25714286 0.27142857 0.28571429 0.3 0.31428571 0.32857143 0.34285714 0.35714286 0.37142857 0.38571429 0.4 0.41428571 0.42857143 0.44285714 0.45714286 0.47142857 0.48571429 0.5 0.51428571 0.52857143 0.54285714 0.55714286 0.57142857 0.58571429 0.6 0.61428571 0.62857143 0.64285714 0.65714286 0.67142857 0.68571429 0.7 0.71428571 0.72857143 0.74285714 0.75714286 0.77142857 0.78571429 0.8 0.81428571 0.82857143 0.84285714 0.85714286 0.87142857 0.88571429 0.9 0.91428571 0.92857143 0.94285714 0.95714286 0.97142857 0.98571429 1 1 1 1 1 1
  arc A4 (-5.340608, -3.616685) -> (-5.209022, -3.803759) centre (0, 0) ccw
  spline S13 degree 5 poles (-5.209022, -3.803759) (-5.206928, -3.803399) (-5.202741, -3.802674) (-5.196467, -3.801575) (-5.188114, -3.800088) (-5.177694, -3.798193) (-5.167294, -3.79626) (-5.156916, -3.794291) (-5.146558, -3.792285) (-5.136221, -3.790241) (-5.125906, -3.78816) (-5.115613, -3.786041) (-5.105341, -3.783885) (-5.095092, -3.781691) (-5.084865, -3.779458) (-5.07466, -3.777188) (-5.064479, -3.774879) (-5.05432, -3.772532) (-5.044184, -3.770146) (-5.034072, -3.767721) (-5.023984, -3.765257) (-5.013919, -3.762753) (-5.003879, -3.760211) (-4.993863, -3.757628) (-4.983871, -3.755005) (-4.973905, -3.752342) (-4.963964, -3.749639) (-4.954049, -3.746895) (-4.944159, -3.74411) (-4.934296, -3.741284) (-4.924459, -3.738416) (-4.914649, -3.735507) (-4.904866, -3.732555) (-4.89511, -3.72956) (-4.885383, -3.726523) (-4.875683, -3.723442) (-4.866012, -3.720318) (-4.85637, -3.717151) (-4.846757, -3.713939) (-4.837174, -3.710682) (-4.827622, -3.70738) (-4.818101, -3.704031) (-4.808611, -3.700636) (-4.799153, -3.697193) (-4.789728, -3.693703) (-4.780335, -3.690166) (-4.770974, -3.68658) (-4.761647, -3.682947) (-4.752355, -3.679265) (-4.743097, -3.675531) (-4.733877, -3.671745) (-4.724696, -3.667903) (-4.715554, -3.664005) (-4.706453, -3.66005) (-4.697391, -3.65604) (-4.688368, -3.651975) (-4.679384, -3.647858) (-4.670438, -3.643687) (-4.661533, -3.639461) (-4.652674, -3.63517) (-4.643869, -3.630807) (-4.635122, -3.626362) (-4.62799, -3.622641) (-4.622625, -3.619784) (-4.619, -3.61783) (-4.617099, -3.616799) (-4.616916, -3.6167) knots -1 -1 -1 -1 -1 -1 -0.98571429 -0.97142857 -0.95714286 -0.94285714 -0.92857143 -0.91428571 -0.9 -0.88571429 -0.87142857 -0.85714286 -0.84285714 -0.82857143 -0.81428571 -0.8 -0.78571429 -0.77142857 -0.75714286 -0.74285714 -0.72857143 -0.71428571 -0.7 -0.68571429 -0.67142857 -0.65714286 -0.64285714 -0.62857143 -0.61428571 -0.6 -0.58571429 -0.57142857 -0.55714286 -0.54285714 -0.52857143 -0.51428571 -0.5 -0.48571429 -0.47142857 -0.45714286 -0.44285714 -0.42857143 -0.41428571 -0.4 -0.38571429 -0.37142857 -0.35714286 -0.34285714 -0.32857143 -0.31428571 -0.3 -0.28571429 -0.27142857 -0.25714286 -0.24285714 -0.22857143 -0.21428571 -0.2 -0.18571429 -0.17142857 -0.15714286 -0.14285714 -0.12857143 -0.1270499 -0.1270499 -0.1270499 -0.1270499 -0.1270499 -0.1270499
  spline S14 degree 3 poles (-4.429564, -3.843877) (-4.417149, -3.828798) (-4.407798, -3.811438) (-4.396276, -3.774112) (-4.394216, -3.754502) (-4.397728, -3.715595) (-4.403267, -3.696671) (-4.421287, -3.662011) (-4.433596, -3.646607) (-4.463426, -3.621383) (-4.480661, -3.611805) (-4.517834, -3.599795) (-4.537415, -3.597477) (-4.567377, -3.599786) (-4.57775, -3.601695) (-4.597925, -3.607652) (-4.607671, -3.611683) (-4.616916, -3.6167) knots 0 0 0 0 0.00585967 0.00585967 0.01171933 0.01171933 0.017579 0.017579 0.02343867 0.02343867 0.02929834 0.02929834 0.035158 0.035158 0.03831344 0.03831344 0.04146887 0.04146887 0.04146887 0.04146887
  spline S15 degree 5 poles (-4.429564, -3.843877) (-4.429696, -3.844038) (-4.43107, -3.845708) (-4.433679, -3.848895) (-4.437505, -3.853618) (-4.442516, -3.859911) (-4.448545, -3.867651) (-4.454505, -3.875465) (-4.460403, -3.883345) (-4.466248, -3.891282) (-4.472045, -3.89927) (-4.477798, -3.907307) (-4.483506, -3.915391) (-4.489169, -3.923523) (-4.494784, -3.931705) (-4.500351, -3.939937) (-4.505871, -3.948219) (-4.511343, -3.95655) (-4.516771, -3.964927) (-4.522155, -3.973349) (-4.527498, -3.981813) (-4.532799, -3.99032) (-4.538061, -3.998867) (-4.543281, -4.007456) (-4.548462, -4.016085) (-4.553602, -4.024755) (-4.558702, -4.033464) (-4.563762, -4.042214) (-4.568784, -4.051001) (-4.573767, -4.059827) (-4.578713, -4.068689) (-4.583621, -4.077589) (-4.588492, -4.086524) (-4.593326, -4.095495) (-4.598123, -4.104502) (-4.602883, -4.113544) (-4.607608, -4.122621) (-4.612296, -4.131732) (-4.616948, -4.140877) (-4.621565, -4.150055) (-4.626147, -4.159267) (-4.630693, -4.168512) (-4.635205, -4.177788) (-4.639682, -4.187098) (-4.644124, -4.196439) (-4.648532, -4.205811) (-4.652906, -4.215215) (-4.657246, -4.22465) (-4.661551, -4.234115) (-4.665824, -4.243611) (-4.670062, -4.253137) (-4.674267, -4.262693) (-4.678439, -4.272279) (-4.682577, -4.281894) (-4.686683, -4.291538) (-4.690755, -4.301211) (-4.694795, -4.310913) (-4.698802, -4.320643) (-4.702776, -4.330401) (-4.706718, -4.340188) (-4.710627, -4.350002) (-4.714504, -4.359843) (-4.718349, -4.369712) (-4.721399, -4.377629) (-4.723672, -4.383579) (-4.725181, -4.387551) (-4.725934, -4.389539) knots 0.1270499 0.1270499 0.1270499 0.1270499 0.1270499 0.1270499 0.12857143 0.14285714 0.15714286 0.17142857 0.18571429 0.2 0.21428571 0.22857143 0.24285714 0.25714286 0.27142857 0.28571429 0.3 0.31428571 0.32857143 0.34285714 0.35714286 0.37142857 0.38571429 0.4 0.41428571 0.42857143 0.44285714 0.45714286 0.47142857 0.48571429 0.5 0.51428571 0.52857143 0.54285714 0.55714286 0.57142857 0.58571429 0.6 0.61428571 0.62857143 0.64285714 0.65714286 0.67142857 0.68571429 0.7 0.71428571 0.72857143 0.74285714 0.75714286 0.77142857 0.78571429 0.8 0.81428571 0.82857143 0.84285714 0.85714286 0.87142857 0.88571429 0.9 0.91428571 0.92857143 0.94285714 0.95714286 0.97142857 0.98571429 1 1 1 1 1 1
  arc A5 (-4.725934, -4.389539) -> (-4.567334, -4.554334) centre (0, 0) ccw
  spline S16 degree 5 poles (-4.567334, -4.554334) (-4.565319, -4.553658) (-4.561292, -4.552303) (-4.555259, -4.550259) (-4.547231, -4.547515) (-4.537222, -4.544051) (-4.527239, -4.540554) (-4.517283, -4.537023) (-4.507353, -4.533459) (-4.497449, -4.529861) (-4.487573, -4.52623) (-4.477724, -4.522565) (-4.467902, -4.518866) (-4.458107, -4.515133) (-4.448341, -4.511366) (-4.438602, -4.507564) (-4.428892, -4.503728) (-4.419211, -4.499858) (-4.409558, -4.495952) (-4.399935, -4.492012) (-4.390341, -4.488037) (-4.380776, -4.484027) (-4.371242, -4.479981) (-4.361738, -4.4759) (-4.352264, -4.471783) (-4.342821, -4.46763) (-4.333409, -4.46344) (-4.324029, -4.459215) (-4.31468, -4.454953) (-4.305364, -4.450654) (-4.29608, -4.446319) (-4.286829, -4.441946) (-4.277611, -4.437535) (-4.268427, -4.433086) (-4.259277, -4.4286) (-4.250162, -4.424075) (-4.241081, -4.419511) (-4.232035, -4.414909) (-4.223025, -4.410267) (-4.214052, -4.405586) (-4.205115, -4.400864) (-4.196217, -4.396101) (-4.187356, -4.391297) (-4.178535, -4.386451) (-4.169753, -4.381563) (-4.16101, -4.376633) (-4.152307, -4.371661) (-4.143644, -4.366647) (-4.135022, -4.361589) (-4.126443, -4.356486) (-4.117909, -4.351337) (-4.109421, -4.346139) (-4.100982, -4.340891) (-4.092591, -4.335593) (-4.084248, -4.330246) (-4.075951, -4.324851) (-4.0677, -4.319411) (-4.059496, -4.313924) (-4.051341, -4.308388) (-4.043241, -4.302795) (-4.035205, -4.297139) (-4.027239, -4.291411) (-4.020759, -4.286644) (-4.015892, -4.283002) (-4.012608, -4.280518) (-4.010886, -4.279209) (-4.010721, -4.279082) knots -1 -1 -1 -1 -1 -1 -0.98571429 -0.97142857 -0.95714286 -0.94285714 -0.92857143 -0.91428571 -0.9 -0.88571429 -0.87142857 -0.85714286 -0.84285714 -0.82857143 -0.81428571 -0.8 -0.78571429 -0.77142857 -0.75714286 -0.74285714 -0.72857143 -0.71428571 -0.7 -0.68571429 -0.67142857 -0.65714286 -0.64285714 -0.62857143 -0.61428571 -0.6 -0.58571429 -0.57142857 -0.55714286 -0.54285714 -0.52857143 -0.51428571 -0.5 -0.48571429 -0.47142857 -0.45714286 -0.44285714 -0.42857143 -0.41428571 -0.4 -0.38571429 -0.37142857 -0.35714286 -0.34285714 -0.32857143 -0.31428571 -0.3 -0.28571429 -0.27142857 -0.25714286 -0.24285714 -0.22857143 -0.21428571 -0.2 -0.18571429 -0.17142857 -0.15714286 -0.14285714 -0.12857143 -0.1270499 -0.1270499 -0.1270499 -0.1270499 -0.1270499 -0.1270499
  spline S17 degree 3 poles (-3.790886, -4.474998) (-3.780919, -4.458201) (-3.774327, -4.439617) (-3.768639, -4.400969) (-3.769596, -4.381274) (-3.779006, -4.34336) (-3.787369, -4.325503) (-3.810468, -4.294) (-3.824984, -4.280655) (-3.858315, -4.260281) (-3.87681, -4.253446) (-3.91538, -4.247251) (-3.935086, -4.24795) (-3.964344, -4.254805) (-3.974304, -4.258275) (-3.993334, -4.267241) (-4.002351, -4.272713) (-4.010721, -4.279082) knots 0 0 0 0 0.00585967 0.00585967 0.01171933 0.01171933 0.017579 0.017579 0.02343867 0.02343867 0.02929834 0.02929834 0.035158 0.035158 0.03831344 0.03831344 0.04146887 0.04146887 0.04146887 0.04146887
  spline S18 degree 5 poles (-3.790886, -4.474998) (-3.790993, -4.475177) (-3.792096, -4.477037) (-3.794187, -4.480585) (-3.797247, -4.485837) (-3.801239, -4.492821) (-3.806015, -4.501391) (-3.810713, -4.510023) (-3.81534, -4.518711) (-3.819904, -4.527447) (-3.824414, -4.536227) (-3.828872, -4.545047) (-3.83328, -4.553908) (-3.837634, -4.562809) (-3.841935, -4.571752) (-3.846181, -4.580738) (-3.850371, -4.589766) (-3.854508, -4.598834) (-3.858593, -4.607941) (-3.862629, -4.617086) (-3.866616, -4.626267) (-3.870558, -4.635483) (-3.874452, -4.644734) (-3.878301, -4.654019) (-3.882103, -4.663338) (-3.88586, -4.67269) (-3.88957, -4.682077) (-3.893236, -4.691496) (-3.896857, -4.700947) (-3.900435, -4.71043) (-3.90397, -4.719943) (-3.907462, -4.729487) (-3.910912, -4.739062) (-3.914319, -4.748666) (-3.917685, -4.758299) (-3.92101, -4.767962) (-3.924293, -4.777653) (-3.927536, -4.787373) (-3.930738, -4.797121) (-3.933899, -4.806897) (-3.937021, -4.8167) (-3.940103, -4.82653) (-3.943146, -4.836387) (-3.946149, -4.846271) (-3.949113, -4.85618) (-3.952039, -4.866116) (-3.954926, -4.876077) (-3.957775, -4.886064) (-3.960585, -4.896076) (-3.963358, -4.906113) (-3.966093, -4.916174) (-3.96879, -4.92626) (-3.971449, -4.93637) (-3.974072, -4.946504) (-3.976657, -4.956662) (-3.979205, -4.966843) (-3.981716, -4.977048) (-3.984191, -4.987276) (-3.986629, -4.997526) (-3.989031, -5.0078) (-3.991396, -5.018095) (-3.993725, -5.028413) (-3.996018, -5.038753) (-3.997824, -5.047043) (-3.999162, -5.053271) (-4.000047, -5.057427) (-4.000488, -5.059506) knots 0.1270499 0.1270499 0.1270499 0.1270499 0.1270499 0.1270499 0.12857143 0.14285714 0.15714286 0.17142857 0.18571429 0.2 0.21428571 0.22857143 0.24285714 0.25714286 0.27142857 0.28571429 0.3 0.31428571 0.32857143 0.34285714 0.35714286 0.37142857 0.38571429 0.4 0.41428571 0.42857143 0.44285714 0.45714286 0.47142857 0.48571429 0.5 0.51428571 0.52857143 0.54285714 0.55714286 0.57142857 0.58571429 0.6 0.61428571 0.62857143 0.64285714 0.65714286 0.67142857 0.68571429 0.7 0.71428571 0.72857143 0.74285714 0.75714286 0.77142857 0.78571429 0.8 0.81428571 0.82857143 0.84285714 0.85714286 0.87142857 0.88571429 0.9 0.91428571 0.92857143 0.94285714 0.95714286 0.97142857 0.98571429 1 1 1 1 1 1
  arc A6 (-4.000488, -5.059506) -> (-3.818591, -5.19816) centre (0, 0) ccw
  spline S19 degree 5 poles (-3.818591, -5.19816) (-3.816703, -5.197184) (-3.81293, -5.195229) (-3.80728, -5.192289) (-3.799765, -5.188351) (-3.790402, -5.1834) (-3.78107, -5.17842) (-3.771769, -5.173411) (-3.762499, -5.168373) (-3.753261, -5.163306) (-3.744055, -5.158209) (-3.73488, -5.153084) (-3.725738, -5.147929) (-3.716628, -5.142744) (-3.707551, -5.137531) (-3.698507, -5.132287) (-3.689497, -5.127014) (-3.68052, -5.121711) (-3.671576, -5.116378) (-3.662667, -5.111015) (-3.653792, -5.105622) (-3.644952, -5.100198) (-3.636147, -5.094744) (-3.627377, -5.08926) (-3.618643, -5.083745) (-3.609944, -5.078199) (-3.601282, -5.072623) (-3.592657, -5.067015) (-3.584068, -5.061376) (-3.575517, -5.055705) (-3.567004, -5.050003) (-3.558529, -5.044269) (-3.550093, -5.038503) (-3.541695, -5.032705) (-3.533338, -5.026874) (-3.52502, -5.02101) (-3.516742, -5.015114) (-3.508505, -5.009185) (-3.500309, -5.003222) (-3.492155, -4.997226) (-3.484045, -4.991195) (-3.475977, -4.98513) (-3.467954, -4.97903) (-3.459976, -4.972894) (-3.452043, -4.966723) (-3.444155, -4.960516) (-3.436313, -4.954274) (-3.428517, -4.947996) (-3.420768, -4.941681) (-3.413068, -4.935329) (-3.40542, -4.928937) (-3.397826, -4.922504) (-3.390286, -4.916029) (-3.382803, -4.909513) (-3.375373, -4.902955) (-3.367998, -4.896357) (-3.360674, -4.889721) (-3.353403, -4.883046) (-3.346188, -4.876329) (-3.339037, -4.869566) (-3.331959, -4.862749) (-3.324961, -4.855872) (-3.319284, -4.850173) (-3.31503, -4.845831) (-3.312164, -4.842874) (-3.310662, -4.841317) (-3.310518, -4.841167) knots -1 -1 -1 -1 -1 -1 -0.98571429 -0.97142857 -0.95714286 -0.94285714 -0.92857143 -0.91428571 -0.9 -0.88571429 -0.87142857 -0.85714286 -0.84285714 -0.82857143 -0.81428571 -0.8 -0.78571429 -0.77142857 -0.75714286 -0.74285714 -0.72857143 -0.71428571 -0.7 -0.68571429 -0.67142857 -0.65714286 -0.64285714 -0.62857143 -0.61428571 -0.6 -0.58571429 -0.57142857 -0.55714286 -0.54285714 -0.52857143 -0.51428571 -0.5 -0.48571429 -0.47142857 -0.45714286 -0.44285714 -0.42857143 -0.41428571 -0.4 -0.38571429 -0.37142857 -0.35714286 -0.34285714 -0.32857143 -0.31428571 -0.3 -0.28571429 -0.27142857 -0.25714286 -0.24285714 -0.22857143 -0.21428571 -0.2 -0.18571429 -0.17142857 -0.15714286 -0.14285714 -0.12857143 -0.1270499 -0.1270499 -0.1270499 -0.1270499 -0.1270499 -0.1270499
  spline S20 degree 3 poles (-3.063353, -5.001229) (-3.056067, -4.983107) (-3.052389, -4.963735) (-3.052667, -4.924672) (-3.056619, -4.905354) (-3.071707, -4.86932) (-3.082697, -4.852949) (-3.110335, -4.825342) (-3.126718, -4.814369) (-3.162768, -4.799321) (-3.18209, -4.79539) (-3.221154, -4.795155) (-3.240522, -4.798854) (-3.268391, -4.810095) (-3.277704, -4.815045) (-3.295142, -4.826811) (-3.303218, -4.833595) (-3.310518, -4.841167) knots 0 0 0 0 0.00585967 0.00585967 0.01171933 0.01171933 0.017579 0.017579 0.02343867 0.02343867 0.02929834 0.02929834 0.035158 0.035158 0.03831344 0.03831344 0.04146887 0.04146887 0.04146887 0.04146887
  spline S21 degree 5 poles (-3.063353, -5.001229) (-3.063431, -5.001422) (-3.064237, -5.003429) (-3.065763, -5.007255) (-3.067985, -5.012912) (-3.070864, -5.020424) (-3.074276, -5.029623) (-3.077601, -5.03887) (-3.080847, -5.048162) (-3.084025, -5.057493) (-3.087142, -5.066858) (-3.090201, -5.076256) (-3.093204, -5.085685) (-3.096149, -5.095147) (-3.099035, -5.104642) (-3.101859, -5.11417) (-3.104622, -5.123732) (-3.107326, -5.133325) (-3.109973, -5.14295) (-3.112565, -5.152604) (-3.115105, -5.162286) (-3.117593, -5.171995) (-3.12003, -5.181732) (-3.122416, -5.191495) (-3.124751, -5.201286) (-3.127036, -5.211102) (-3.129271, -5.220945) (-3.131456, -5.230813) (-3.133592, -5.240706) (-3.13568, -5.250624) (-3.137721, -5.260566) (-3.139715, -5.270531) (-3.141663, -5.28052) (-3.143565, -5.290531) (-3.145421, -5.300566) (-3.147231, -5.310623) (-3.148997, -5.320702) (-3.150717, -5.330803) (-3.152394, -5.340925) (-3.154026, -5.351069) (-3.155615, -5.361234) (-3.15716, -5.371419) (-3.158663, -5.381625) (-3.160122, -5.391851) (-3.161539, -5.402097) (-3.162914, -5.412363) (-3.164246, -5.422648) (-3.165537, -5.432953) (-3.166786, -5.443276) (-3.167994, -5.453619) (-3.169161, -5.46398) (-3.170287, -5.474359) (-3.171372, -5.484757) (-3.172417, -5.495172) (-3.173421, -5.505606) (-3.174385, -5.516057) (-3.175309, -5.526525) (-3.176194, -5.537011) (-3.177039, -5.547514) (-3.177844, -5.558033) (-3.17861, -5.568569) (-3.179337, -5.579122) (-3.180025, -5.589691) (-3.180544, -5.598159) (-3.180916, -5.604518) (-3.181156, -5.60876) (-3.181274, -5.610882) knots 0.1270499 0.1270499 0.1270499 0.1270499 0.1270499 0.1270499 0.12857143 0.14285714 0.15714286 0.17142857 0.18571429 0.2 0.21428571 0.22857143 0.24285714 0.25714286 0.27142857 0.28571429 0.3 0.31428571 0.32857143 0.34285714 0.35714286 0.37142857 0.38571429 0.4 0.41428571 0.42857143 0.44285714 0.45714286 0.47142857 0.48571429 0.5 0.51428571 0.52857143 0.54285714 0.55714286 0.57142857 0.58571429 0.6 0.61428571 0.62857143 0.64285714 0.65714286 0.67142857 0.68571429 0.7 0.71428571 0.72857143 0.74285714 0.75714286 0.77142857 0.78571429 0.8 0.81428571 0.82857143 0.84285714 0.85714286 0.87142857 0.88571429 0.9 0.91428571 0.92857143 0.94285714 0.95714286 0.97142857 0.98571429 1 1 1 1 1 1
  arc A7 (-3.181274, -5.610882) -> (-2.980343, -5.720145) centre (0, 0) ccw